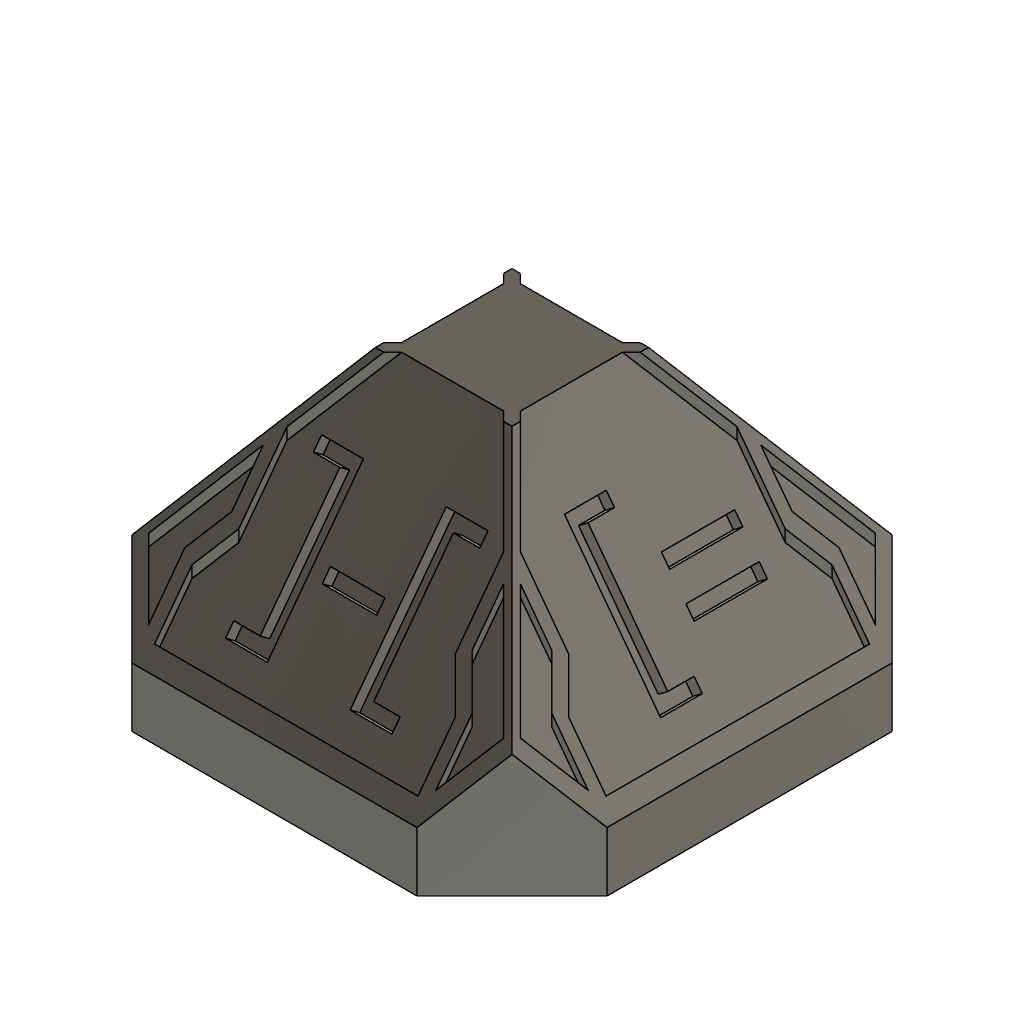
Square Piece (Autodesk Fusion 360 design; units mm, degrees)
part number: 2026-10-12-20-49-09-921
Autodesk Fusion 360 part; units mm, degrees
note: some values were not read from the file. Set by a fixed rule: which face or edge a step refers to.
sketch "Sketch1" plane through (0, 0, 0) normal (0, 0, 1) x (1, 0, 0)
  line L0 (-10, 10) -> (10, 10)
  line L1 (10, 10) -> (10, -10)
  line L2 (10, -10) -> (-10, -10)
  line L3 (-10, -10) -> (-10, 10)
  line L4 (-2.5, 2.5) -> (2.5, 2.5)
  line L5 (2.5, 2.5) -> (2.5, -2.5)
  line L6 (2.5, -2.5) -> (-2.5, -2.5)
  line L7 (-2.5, -2.5) -> (-2.5, 2.5)
  line L8 (-6, 10) -> (-10, 6)
  line L9 (6, 10) -> (10, 6)
  line L10 (10, -6) -> (6, -10)
  line L11 (-10, -6) -> (-6, -10)
  line L12 (-2.5, 2.5) -> (-8, 8)
  line L13 (2.5, 2.5) -> (8, 8)
  line L14 (2.5, -2.5) -> (8, -8)
  line L15 (-2.5, -2.5) -> (-8, -8)
  line L16 (-6.5, 9.5) -> (6.5, 9.5)
  line L17 (9.5, 6.5) -> (9.5, -6.5)
  line L18 (6.5, -9.5) -> (-6.5, -9.5)
  line L19 (-9.5, -6.5) -> (-9.5, 6.5)
  line L20 (-10, 5.2929) -> (-5.2929, 10)
  line L21 (5.2929, 10) -> (10, 5.2929)
  line L22 (10, -5.2929) -> (5.2929, -10)
  line L23 (-5.2929, -10) -> (-10, -5.2929)
  line L24 (2.1464, 2.5) -> (7.4697, 7.8232)
  line L25 (2.5, 2.1464) -> (7.8232, 7.4697)
  line L26 (-2.1464, 2.5) -> (-7.4697, 7.8232)
  line L27 (-2.5, 2.1464) -> (-7.8232, 7.4697)
  line L28 (-2.5, -2.1464) -> (-7.8232, -7.4697)
  line L29 (-2.1464, -2.5) -> (-7.4697, -7.8232)
  line L30 (2.1464, -2.5) -> (7.4697, -7.8232)
  line L31 (2.5, -2.1464) -> (7.8232, -7.4697)
  line L32 (6.4545, 8.8384) -> (4.2354, 6.6193)
  line L33 (6.8081, 8.4848) -> (4.4937, 6.1705)
  line L34 (5.7929, 9.5) -> (5.0889, 8.796)
  line L35 (8.4848, 6.8081) -> (5.9884, 4.3116)
  line L36 (8.8384, 6.4545) -> (6.602, 4.2182)
  line L37 (4.8081, 5.1616) -> (4.8081, 5.9)
  line L38 (5.1616, 4.8081) -> (5.9, 4.8081)
  line L39 (4.5581, 4.9116) -> (4.5581, 6.9428)
  line L40 (5.0581, 5.4116) -> (5.0581, 6.7348)
  line L41 (5.4116, 5.0581) -> (6.7348, 5.0581)
  line L42 (4.9116, 4.5581) -> (6.9419, 4.5581)
  line L43 (9.5, 5.7929) -> (8.9687, 5.2616)
  line L44 (2.5, 0) -> (9.5, 0)
  line L45 (2.5, -2.5) -> (8, -8)
  line L46 (8.4848, -6.8081) -> (5.9884, -4.3116)
  line L47 (6, -10) -> (10, -6)
  line L48 (5.2929, -10) -> (10, -5.2929)
  line L49 (2.5, -2.1464) -> (7.8232, -7.4697)
  line L50 (6.4545, -8.8384) -> (4.2354, -6.6193)
  line L51 (4.8081, -5.1616) -> (4.8081, -5.9)
  line L52 (9.5, -5.7929) -> (8.9687, -5.2616)
  line L53 (5.1616, -4.8081) -> (5.9, -4.8081)
  line L54 (6.8081, -8.4848) -> (4.4937, -6.1705)
  line L55 (5.7929, -9.5) -> (5.0889, -8.796)
  line L56 (2.1464, -2.5) -> (7.4697, -7.8232)
  line L57 (4.5581, -4.9116) -> (4.5581, -6.9428)
  line L58 (5.0581, -5.4116) -> (5.0581, -6.7348)
  line L59 (4.9116, -4.5581) -> (6.9419, -4.5581)
  line L60 (5.4116, -5.0581) -> (6.7348, -5.0581)
  line L61 (8.8384, -6.4545) -> (6.602, -4.2182)
  line L62 (0, 2.5) -> (0, 9.5)
  line L63 (0, -2.5) -> (0, -9.5)
  line L64 (-4.5581, 4.9116) -> (-4.5581, 6.9428)
  line L65 (-5.2929, 10) -> (-10, 5.2929)
  line L66 (-8.8384, 6.4545) -> (-6.602, 4.2182)
  line L67 (-5.4116, 5.0581) -> (-6.7348, 5.0581)
  line L68 (-4.9116, 4.5581) -> (-6.9419, 4.5581)
  line L69 (-2.1464, 2.5) -> (-7.4697, 7.8232)
  line L70 (-6.4545, 8.8384) -> (-4.2354, 6.6193)
  line L71 (-4.8081, 5.1616) -> (-4.8081, 5.9)
  line L72 (-9.5, 5.7929) -> (-8.9687, 5.2616)
  line L73 (-5.7929, 9.5) -> (-5.0889, 8.796)
  line L74 (-5.0581, 5.4116) -> (-5.0581, 6.7348)
  line L75 (-2.5, 2.1464) -> (-7.8232, 7.4697)
  line L76 (-6, 10) -> (-10, 6)
  line L77 (-5.1616, 4.8081) -> (-5.9, 4.8081)
  line L78 (-2.5, 2.5) -> (-8, 8)
  line L79 (-8.4848, 6.8081) -> (-5.9884, 4.3116)
  line L80 (-6.8081, 8.4848) -> (-4.4937, 6.1705)
  line L81 (-10, -5.2929) -> (-5.2929, -10)
  line L82 (-10, 10) -> (-10, -10)
  line L83 (-4.8081, -5.1616) -> (-4.8081, -5.9)
  line L84 (-9.5, 6.5) -> (-9.5, -6.5)
  line L85 (-8.4848, -6.8081) -> (-5.9884, -4.3116)
  line L86 (-5.7929, -9.5) -> (-5.0889, -8.796)
  line L87 (-9.5, -5.7929) -> (-8.9687, -5.2616)
  line L88 (-5.4116, -5.0581) -> (-6.7348, -5.0581)
  line L89 (-2.1464, -2.5) -> (-7.4697, -7.8232)
  line L90 (-10, -6) -> (-6, -10)
  line L91 (-6, -10) -> (-10, -6)
  line L92 (-2.5, -2.1464) -> (-7.8232, -7.4697)
  line L93 (-4.5581, -4.9116) -> (-4.5581, -6.9428)
  line L94 (-2.5, -2.5) -> (-8, -8)
  line L95 (-2.5, -2.5) -> (-8, -8)
  line L96 (-5.1616, -4.8081) -> (-5.9, -4.8081)
  line L97 (-8.8384, -6.4545) -> (-6.602, -4.2182)
  line L98 (-5.0581, -5.4116) -> (-5.0581, -6.7348)
  line L99 (-2.5, -2.1464) -> (-7.8232, -7.4697)
  line L100 (-6.8081, -8.4848) -> (-4.4937, -6.1705)
  line L101 (-4.9116, -4.5581) -> (-6.9419, -4.5581)
  line L102 (-5.2929, -10) -> (-10, -5.2929)
  line L103 (-6.4545, -8.8384) -> (-4.2354, -6.6193)
  line L104 (-2.1464, -2.5) -> (-7.4697, -7.8232)
  line L105 (5.7929, 9.5) -> (5.7929, 8.1768)
  line L106 (5.5429, 9.5) -> (5.5429, 7.9268)
  line L107 (6.0429, 9.25) -> (6.0429, 7.7197)
  line L108 (9.5, 5.7929) -> (8.1768, 5.7929)
  line L109 (7.9268, 5.5429) -> (9.5, 5.5429)
  line L110 (7.7197, 6.0429) -> (9.25, 6.0429)
  line L111 (7.7197, -6.0429) -> (9.25, -6.0429)
  line L112 (9.5, -5.7929) -> (8.1768, -5.7929)
  line L113 (7.9268, -5.5429) -> (9.5, -5.5429)
  line L114 (5.5429, -9.5) -> (5.5429, -7.9268)
  line L115 (5.7929, -9.5) -> (5.7929, -8.1768)
  line L116 (6.0429, -9.25) -> (6.0429, -7.7197)
  line L117 (-7.7197, -6.0429) -> (-9.25, -6.0429)
  line L118 (-9.5, -5.7929) -> (-8.1768, -5.7929)
  line L119 (-7.9268, -5.5429) -> (-9.5, -5.5429)
  line L120 (-6.0429, -9.25) -> (-6.0429, -7.7197)
  line L121 (-5.7929, -9.5) -> (-5.7929, -8.1768)
  line L122 (-5.5429, -9.5) -> (-5.5429, -7.9268)
  line L123 (-7.9268, 5.5429) -> (-9.5, 5.5429)
  line L124 (-9.5, 5.7929) -> (-8.1768, 5.7929)
  line L125 (-7.7197, 6.0429) -> (-9.25, 6.0429)
  line L126 (-6.0429, 9.25) -> (-6.0429, 7.7197)
  line L127 (-5.7929, 9.5) -> (-5.7929, 8.1768)
  line L128 (-5.5429, 9.5) -> (-5.5429, 7.9268)
  point P0 (10, -10)
  point P1 (9.5, -6.5)
  point P2 (6.5, -9.5)
  point P3 (-6.5, 9.5)
  point P4 (-6.5, -9.5)
  point P5 (-6.5, -9.5)
  point P6 (-9.5, -6.5)
  point P7 (-10, -10)
  dimension "d1" = 0.5
  dimension "d2" = 0.5
  dimension "d3" = 0.5
  dimension "d4" = 0.5
  dimension "d5" = 0.25
  dimension "d6" = 0.25
  dimension "d7" = 0.25
  dimension "d8" = 0.25
  dimension "d9" = 0.25
  dimension "d10" = 0.25
  dimension "d11" = 0.25
  dimension "d12" = 0.25
  dimension "d13" = 0.5
  dimension "d17" = 0.5
  dimension "d18" = 0.5
  dimension "d19" = 0.5
  dimension "d20" = 0.5
  dimension "d21" = 4
  dimension "d22" = 4
  dimension "d23" = 4
  dimension "d24" = 4
  dimension "d25" = 4
  dimension "d26" = 20
  dimension "d27" = 20
  dimension "d28" = 4
  dimension "d29" = 4
  dimension "d30" = 4
  dimension "d31" = 0.9357
  dimension "d32" = 0.9357
  dimension "d33" = 0.5
  dimension "d39" = 2.5
  dimension "d40" = 2.5
  dimension "d41" = 2.5
  dimension "d42" = 2.5
  dimension "d46" = 3.7641
  dimension "d47" = 3.7641
  dimension "d48" = 3.7641
  dimension "d49" = 3.7641
  dimension "d50" = 0.25
  dimension "d51" = 0.25
  dimension "d52" = 0.25
  dimension "d53" = 0.25
  dimension "d54" = 0.9357
  dimension "d55" = 0.9357
  dimension "d75" = 0.25
  dimension "d76" = 0.25
  dimension "d77" = 0.25
  dimension "d78" = 0.25
  constraint horizontal L0
  constraint vertical L1
  constraint horizontal L2
  constraint vertical L3
  constraint horizontal L4
  constraint vertical L5
  constraint horizontal L6
  constraint vertical L7
  constraint coincident L0 L8.start
  constraint coincident L3 L8.end
  constraint coincident L0 L9.start
  constraint coincident L1 L9.end
  constraint perpendicular L8 L9
  constraint coincident L1 L10.start
  constraint coincident L2 L10.end
  constraint parallel L8 L10
  constraint coincident L3 L11.start
  constraint coincident L2 L11.end
  constraint perpendicular L10 L11
  constraint midpoint L8 L12.end
  constraint perpendicular L8 L12
  constraint midpoint L9 L13.end
  constraint perpendicular L9 L13
  constraint midpoint L10 L14.end
  constraint perpendicular L10 L14
  constraint midpoint L11 L15.end
  constraint perpendicular L11 L15
  constraint coincident L8 P3
  constraint coincident L9 L16.end
  constraint parallel L0 L16
  constraint coincident L9 L17.start
  constraint coincident L10 P1
  constraint perpendicular L16 L17
  constraint coincident L10 P2
  constraint coincident L11 P5
  constraint perpendicular L1 L18
  constraint coincident L11 P6
  constraint coincident L8 L19.end
  constraint perpendicular L18 L19
  constraint coincident L3 L20.start
  constraint coincident L0 L20.end
  constraint coincident L0 L21.start
  constraint coincident L1 L21.end
  constraint perpendicular L13 L21
  constraint coincident L1 L22.start
  constraint coincident L2 L22.end
  constraint perpendicular L21 L22
  constraint coincident L2 L23.start
  constraint coincident L3 L23.end
  constraint perpendicular L22 L23
  constraint coincident L4 L24.start
  constraint coincident L21 L24.end
  constraint perpendicular L21 L24
  constraint coincident L5 L25.start
  constraint coincident L21 L25.end
  constraint perpendicular L21 L25
  constraint coincident L4 L26.start
  constraint coincident L20 L26.end
  constraint perpendicular L20 L26
  constraint coincident L7 L27.start
  constraint coincident L20 L27.end
  constraint perpendicular L20 L27
  constraint coincident L7 L28.start
  constraint coincident L23 L28.end
  constraint perpendicular L23 L28
  constraint coincident L6 L29.start
  constraint coincident L23 L29.end
  constraint perpendicular L23 L29
  constraint coincident L6 L30.start
  constraint coincident L22 L30.end
  constraint perpendicular L22 L30
  constraint coincident L5 L31.start
  constraint coincident L22 L31.end
  constraint perpendicular L22 L31
  constraint coincident L21 L32.start
  constraint perpendicular L21 L32
  constraint coincident L21 L33.start
  constraint perpendicular L21 L33
  constraint coincident L21 L34.start
  constraint coincident L16 L34.start
  constraint perpendicular L21 L34
  constraint coincident L21 L35.start
  constraint perpendicular L21 L35
  constraint coincident L21 L36.start
  constraint perpendicular L21 L36
  constraint coincident L24 L37.start
  constraint vertical L37
  constraint coincident L25 L38.start
  constraint horizontal L38
  constraint coincident L24 L39.start
  constraint vertical L39
  constraint coincident L24 L40.start
  constraint parallel L37 L40
  constraint coincident L33 L40.end
  constraint coincident L25 L41.start
  constraint horizontal L41
  constraint coincident L25 L42.start
  constraint horizontal L42
  constraint coincident L21 L43.start
  constraint coincident L17 L43.start
  constraint perpendicular L21 L43
  constraint coincident L36 L42.end
  constraint coincident L35 L41.end
  constraint midpoint L5 L44.start
  constraint midpoint L17 L44.end
  constraint symmetric L0.end L44 P0
  constraint symmetric L4.end L44 L5.end
  constraint symmetric L9.start L44 L10.end
  constraint symmetric L9.end L44 L10.start
  constraint symmetric L13.end L44 L14.end
  constraint symmetric L16.end L44 P2
  constraint symmetric L17.start L44 P1
  constraint symmetric L21.start L44 L22.end
  constraint symmetric L21.end L44 L22.start
  constraint symmetric L24.start L44 L30.start
  constraint symmetric L24.end L44 L30.end
  constraint symmetric L25.start L44 L31.start
  constraint symmetric L25.end L44 L31.end
  constraint symmetric L32.start L44 L50.start
  constraint symmetric L32.end L44 L50.end
  constraint symmetric L33.start L44 L54.start
  constraint symmetric L33.end L44 L54.end
  constraint symmetric L34.start L44 L55.start
  constraint symmetric L34.end L44 L55.end
  constraint symmetric L35.start L44 L46.start
  constraint symmetric L35.end L44 L46.end
  constraint symmetric L36.start L44 L61.start
  constraint symmetric L36.end L44 L61.end
  constraint symmetric L37.start L44 L51.start
  constraint symmetric L37.end L44 L51.end
  constraint symmetric L38.start L44 L53.start
  constraint symmetric L38.end L44 L53.end
  constraint symmetric L39.start L44 L57.start
  constraint symmetric L39.end L44 L57.end
  constraint symmetric L40.start L44 L58.start
  constraint symmetric L40.end L44 L58.end
  constraint symmetric L41.start L44 L60.start
  constraint symmetric L41.end L44 L60.end
  constraint symmetric L42.start L44 L59.start
  constraint symmetric L42.end L44 L59.end
  constraint symmetric L43.start L44 L52.start
  constraint symmetric L43.end L44 L52.end
  constraint midpoint L4 L62.start
  constraint midpoint L16 L62.end
  constraint midpoint L6 L63.start
  constraint midpoint L18 L63.end
  constraint symmetric L0.end L62 L0.start
  constraint symmetric P0 L62 P7
  constraint symmetric L4.end L62 L4.start
  constraint symmetric L5.end L62 L6.end
  constraint symmetric L9.start L62 L8.start
  constraint symmetric L9.end L62 L8.end
  constraint symmetric L10.start L62 L11.start
  constraint symmetric L10.end L62 L11.end
  constraint symmetric L13.end L62 L12.end
  constraint symmetric L14.end L62 L15.end
  constraint symmetric L16.end L62 P3
  constraint symmetric L17.start L62 L19.end
  constraint symmetric P1 L62 P6
  constraint symmetric P2 L62 P5
  constraint symmetric L21.start L62 L20.end
  constraint symmetric L21.end L62 L20.start
  constraint symmetric L22.start L62 L23.end
  constraint symmetric L22.end L62 L23.start
  constraint symmetric L24.start L62 L26.start
  constraint symmetric L24.end L62 L26.end
  constraint symmetric L25.start L62 L27.start
  constraint symmetric L25.end L62 L27.end
  constraint symmetric L30.start L62 L29.start
  constraint symmetric L30.end L62 L29.end
  constraint symmetric L31.start L62 L28.start
  constraint symmetric L31.end L62 L28.end
  constraint symmetric L32.start L62 L70.start
  constraint symmetric L32.end L62 L70.end
  constraint symmetric L33.start L62 L80.start
  constraint symmetric L33.end L62 L80.end
  constraint symmetric L34.start L62 L73.start
  constraint symmetric L34.end L62 L73.end
  constraint symmetric L35.start L62 L79.start
  constraint symmetric L35.end L62 L79.end
  constraint symmetric L36.start L62 L66.start
  constraint symmetric L36.end L62 L66.end
  constraint symmetric L37.start L62 L71.start
  constraint symmetric L37.end L62 L71.end
  constraint symmetric L38.start L62 L77.start
  constraint symmetric L38.end L62 L77.end
  constraint symmetric L39.start L62 L64.start
  constraint symmetric L39.end L62 L64.end
  constraint symmetric L40.start L62 L74.start
  constraint symmetric L40.end L62 L74.end
  constraint symmetric L41.start L62 L67.start
  constraint symmetric L41.end L62 L67.end
  constraint symmetric L42.start L62 L68.start
  constraint symmetric L42.end L62 L68.end
  constraint symmetric L43.start L62 L72.start
  constraint symmetric L43.end L62 L72.end
  constraint symmetric L59.end L62 L101.end
  constraint symmetric L60.end L62 L88.end
  constraint symmetric L59.start L62 L101.start
  constraint symmetric L60.start L62 L88.start
  constraint symmetric L58.start L62 L98.start
  constraint symmetric L52.start L62 L87.start
  constraint symmetric L57.start L62 L93.start
  constraint symmetric L53.start L62 L96.start
  constraint symmetric L51.start L62 L83.start
  constraint symmetric L58.end L62 L98.end
  constraint symmetric L61.start L62 L97.start
  constraint symmetric L55.end L62 L86.end
  constraint symmetric L50.start L62 L103.start
  constraint symmetric L46.start L62 L85.start
  constraint symmetric L55.start L62 L86.start
  constraint symmetric L54.start L62 L100.start
  constraint symmetric L57.end L62 L93.end
  constraint symmetric L54.end L62 L100.end
  constraint symmetric L46.end L62 L85.end
  constraint symmetric L51.end L62 L83.end
  constraint symmetric L50.end L62 L103.end
  constraint symmetric L61.end L62 L97.end
  constraint symmetric L52.end L62 L87.end
  constraint symmetric L53.end L62 L96.end
  constraint coincident L32 L105.end
  constraint vertical L105
  constraint coincident L16 L106.start
  constraint coincident L32 L106.end
  constraint perpendicular L16 L106
  constraint coincident L21 L107.start
  constraint coincident L33 L107.end
  constraint parallel L106 L107
  constraint coincident L36 L108.end
  constraint horizontal L108
  constraint coincident L36 L109.start
  constraint coincident L17 L109.end
  constraint perpendicular L17 L109
  constraint coincident L35 L110.start
  constraint coincident L21 L110.end
  constraint horizontal L110
  constraint symmetric L44 L105.end L115.end
  constraint symmetric L44 L106.start L114.start
  constraint symmetric L44 L106.end L114.end
  constraint symmetric L44 L107.start L116.start
  constraint symmetric L44 L107.end L116.end
  constraint symmetric L44 L108.end L112.end
  constraint symmetric L44 L109.start L113.start
  constraint symmetric L44 L109.end L113.end
  constraint symmetric L44 L110.start L111.start
  constraint symmetric L44 L110.end L111.end
  constraint symmetric L62 L105.end L127.end
  constraint symmetric L62 L106.start L128.start
  constraint symmetric L62 L106.end L128.end
  constraint symmetric L62 L107.start L126.start
  constraint symmetric L62 L107.end L126.end
  constraint symmetric L62 L108.end L124.end
  constraint symmetric L62 L109.start L123.start
  constraint symmetric L62 L109.end L123.end
  constraint symmetric L62 L110.start L125.start
  constraint symmetric L62 L110.end L125.end
  constraint symmetric L62 L111.start L117.start
  constraint symmetric L62 L111.end L117.end
  constraint symmetric L62 L52.start L87.start
  constraint symmetric L62 L112.end L118.end
  constraint symmetric L62 L113.start L119.start
  constraint symmetric L62 L113.end L119.end
  constraint symmetric L62 L114.start L122.start
  constraint symmetric L62 L114.end L122.end
  constraint symmetric L62 L55.start L86.start
  constraint symmetric L62 L115.end L121.end
  constraint symmetric L62 L116.start L120.start
  constraint symmetric L62 L116.end L120.end
  measures "d1" distance of L8 L20
  measures "d2" distance of L9 L21
  measures "d3" distance of L10 L22
  measures "d4" distance of L11 L23
  measures "d5" distance of L13 L24
  measures "d6" distance of L13 L25
  measures "d7" distance of L12 L26
  measures "d8" distance of L12 L27
  measures "d9" distance of L14 L31
  measures "d10" distance of L14 L30
  measures "d11" distance of L15 L29
  measures "d12" distance of L15 L28
  measures "d13" distance of L32 L33
  measures "d17" distance of L0 L16
  measures "d18" distance of L1 L17
  measures "d19" distance of L2 L18
  measures "d20" distance of L3 L19
  measures "d21" distance of L0.end L9.start
  measures "d22" distance of L0.end L9.end
  measures "d23" distance of P0 L10.start
  measures "d24" distance of L0.start L8.start
  measures "d25" distance of P7 L11.start
  measures "d26" distance of L0 L2
  measures "d27" distance of L1 L3
  measures "d28" distance of L0.start L8.end
  measures "d29" distance of P0 L10.end L5
  measures "d30" distance of P7 L11.end
  measures "d31" distance of L24 L33
  measures "d32" distance of L32 L34
  measures "d33" distance of L35 L36
  measures "d39" distance of origin L4
  measures "d40" distance of origin L7
  measures "d41" distance of origin L5
  measures "d42" distance of origin L6
  measures "d46" distance of L21 L37.start
  measures "d47" distance of L24.start L37.start
  measures "d48" distance of L25.start L38.start
  measures "d49" distance of L21 L38.start
  measures "d50" distance of L37 L39
  measures "d51" distance of L37 L40
  measures "d52" distance of L38 L41
  measures "d53" distance of L38 L42
  measures "d54" distance of L36 L43
  measures "d55" distance of L25 L35
  measures "d75" distance of L105 L106
  measures "d76" distance of L105 L107
  measures "d77" distance of L108 L110
  measures "d78" distance of L108 L109
extrude "Extrude1" add sketch "Sketch1" along normal blind 12 contours L0 L8 L16 L20 L65 L76 | L3 L8 L19 L20 L65 L76 L82 L84 | L0 L16 L20 L21 L65 | L8 L12 L16 L20 L65 L76 L78 | L3 L19 L20 L23 L65 L81 L82 L84 L102 | L8 L12 L19 L20 L65 L76 L78 L84 | L0 L9 L16 L21 | L20 L65 L70 L126 L127 | L16 L73 L128 | L70 L73 L127 L128 | L3 L11 L19 L23 L81 L82 L84 L90 L91 L102 | L19 L72 L84 L123 | L66 L72 L123 L124 | L20 L65 L66 L124 L125 | L16 L34 L106 | L9 L13 L16 L21 | L32 L34 L105 L106 | L21 L32 L105 L107 | L4 L16 L26 L62 L64 L69 L70 L128 | L20 L65 L70 L126 | L64 L70 L80 L126 | L4 L12 L20 L26 L65 L69 L78 | L7 L12 L20 L27 L65 L75 L78 | L11 L15 L19 L23 L81 L84 L90 L91 L94 L95 L102 | L23 L81 L97 L102 L117 L118 | L19 L84 L87 L119 | L87 L97 L118 L119 | L7 L19 L27 L28 L66 L68 L75 L84 L92 L97 L99 L101 L119 L123 | L20 L65 L66 L125 | L66 L68 L79 L125 | L4 L16 L24 L32 L39 L62 L106 | L21 L32 L107 | L32 L33 L39 L107 | L20 L65 L70 L80 L126 | L4 L5 L6 L7 | L20 L27 L65 L67 L75 L79 | L20 L26 L65 L69 L74 L80 | L23 L81 L97 L102 L117 | L85 L97 L101 L117 | L20 L65 L66 L79 L125 | L1 L9 L17 L21 | L9 L13 L17 L21 | L21 L32 L33 L107 | L27 L67 L68 L75 L79 | L26 L64 L69 L74 L80 | L2 L11 L18 L23 L81 L90 L91 L102 | L11 L15 L18 L23 L81 L90 L91 L94 L95 L102 | L23 L81 L85 L97 L102 L117 | L1 L17 L21 L22 L48 | L5 L13 L21 L25 | L4 L13 L21 L24 | L21 L24 L33 L40 | L7 L15 L23 L28 L81 L92 L94 L95 L99 L102 | L2 L18 L22 L23 L48 L81 L102 | L6 L15 L23 L29 L81 L89 L94 L95 L102 L104 | L23 L28 L81 L85 L88 L92 L99 L102 | L1 L10 L17 L22 L47 L48 | L21 L36 L108 L110 | L17 L43 L109 | L36 L43 L108 L109 | L21 L25 L35 L41 | L24 L33 L39 L40 | L28 L85 L88 L92 L99 L101 | L2 L10 L18 L22 L47 L48 | L18 L86 L122 | L86 L103 L121 L122 | L23 L81 L102 L103 L120 L121 | L23 L29 L81 L89 L98 L100 L102 L104 | L17 L52 L113 | L10 L14 L17 L22 L45 L47 L48 | L52 L61 L112 L113 | L22 L48 L61 L111 L112 | L5 L17 L25 L36 L42 L44 L109 | L21 L36 L110 | L35 L36 L42 L110 | L21 L35 L36 L110 | L25 L35 L41 L42 | L6 L18 L29 L63 L89 L93 L103 L104 L122 | L10 L14 L18 L22 L45 L47 L48 | L22 L48 L50 L115 L116 | L18 L55 L114 | L50 L55 L114 L115 | L23 L81 L102 L103 L120 | L93 L100 L103 L120 | L23 L81 L100 L102 L103 L120 | L29 L89 L93 L98 L100 L104 | L5 L17 L31 L44 L49 L59 L61 L113 | L22 L48 L61 L111 | L46 L59 L61 L111 | L6 L18 L30 L50 L56 L57 L63 L114 | L22 L48 L50 L116 | L50 L54 L57 L116 | L22 L46 L48 L61 L111 | L5 L14 L22 L31 L45 L48 L49 | L6 L14 L22 L30 L45 L48 L56 | L22 L48 L50 L54 L116 | L22 L31 L46 L48 L49 L60 | L31 L46 L49 L59 L60 | L30 L54 L56 L57 L58 | L22 L30 L48 L54 L56 L58 makes body 1
extrude "Extrude2" add sketch "Sketch1" along normal blind 12 separate body contours L0 L8 L16 L20 L65 L76 | L3 L8 L19 L20 L65 L76 L82 L84 | L0 L16 L20 L21 L65 | L8 L12 L16 L20 L65 L76 L78 | L3 L19 L20 L23 L65 L81 L82 L84 L102 | L8 L12 L19 L20 L65 L76 L78 L84 | L0 L9 L16 L21 | L20 L65 L70 L126 L127 | L16 L73 L128 | L70 L73 L127 L128 | L3 L11 L19 L23 L81 L82 L84 L90 L91 L102 | L19 L72 L84 L123 | L66 L72 L123 L124 | L20 L65 L66 L124 L125 | L16 L34 L106 | L9 L13 L16 L21 | L32 L34 L105 L106 | L21 L32 L105 L107 | L64 L70 L80 L126 | L4 L12 L20 L26 L65 L69 L78 | L7 L12 L20 L27 L65 L75 L78 | L11 L15 L19 L23 L81 L84 L90 L91 L94 L95 L102 | L23 L81 L97 L102 L117 L118 | L19 L84 L87 L119 | L87 L97 L118 L119 | L66 L68 L79 L125 | L32 L33 L39 L107 | L4 L5 L6 L7 | L85 L97 L101 L117 | L1 L9 L17 L21 | L9 L13 L17 L21 | L27 L67 L68 L75 L79 | L26 L64 L69 L74 L80 | L2 L11 L18 L23 L81 L90 L91 L102 | L11 L15 L18 L23 L81 L90 L91 L94 L95 L102 | L1 L17 L21 L22 L48 | L5 L13 L21 L25 | L4 L13 L21 L24 | L7 L15 L23 L28 L81 L92 L94 L95 L99 L102 | L2 L18 L22 L23 L48 L81 L102 | L6 L15 L23 L29 L81 L89 L94 L95 L102 L104 | L1 L10 L17 L22 L47 L48 | L21 L36 L108 L110 | L17 L43 L109 | L36 L43 L108 L109 | L24 L33 L39 L40 | L28 L85 L88 L92 L99 L101 | L2 L10 L18 L22 L47 L48 | L18 L86 L122 | L86 L103 L121 L122 | L23 L81 L102 L103 L120 L121 | L17 L52 L113 | L10 L14 L17 L22 L45 L47 L48 | L52 L61 L112 L113 | L22 L48 L61 L111 L112 | L35 L36 L42 L110 | L25 L35 L41 L42 | L10 L14 L18 L22 L45 L47 L48 | L22 L48 L50 L115 L116 | L18 L55 L114 | L50 L55 L114 L115 | L93 L100 L103 L120 | L29 L89 L93 L98 L100 L104 | L46 L59 L61 L111 | L50 L54 L57 L116 | L5 L14 L22 L31 L45 L48 L49 | L6 L14 L22 L30 L45 L48 L56 | L31 L46 L49 L59 L60 | L30 L54 L56 L57 L58 makes body 2
extrude "Extrude3" add sketch "Sketch1" along normal blind 12 separate body makes body 3
move_body "Move1" bodies 3 to x (1, 0, 0) y (0, 1, 0) z (0, 0, 1) at (0, 0, 7)
move_body "Move2" bodies 3 to x (1, 0, 0) y (0, 1, 0) z (0, 0, 1) at (0, 0, -7)
chamfer "Chamfer1" distance 7.5 distance2 10 104 faces at (-8.1667, 9.1667, 12) (-6.0976, 9.6667, 12) (-7.1027, 8.6616, 12) (-8.6616, 7.1027, 12) (-9.8333, 5.6953, 12) (0, 9.8333, 12) (-5.8762, 8.9756, 12) (-6.1801, 8.8384, 12) (-6.2979, 8.2104, 12) (-6.1902, 6.9848, 12) (-5.0682, 5.186, 12) (-5.0194, 4.9015, 12) (-6.9848, 6.1902, 12) (-8.2104, 6.2979, 12) (-8.8384, 6.1801, 12) (-8.9756, 5.8762, 12) (-9.6667, 1.7643, 12) (5.6953, 9.8333, 12) (5.6262, 9.4167, 12) (1.5194, 6.0783, 12) (-1.5194, 6.0783, 12) (-5.6262, 9.4167, 12) (-5.6262, 8.4512, 12) (-5.053, 7.2015, 12) (-4.8914, 6.1271, 12) (0.8333, 0, 12) (-4.9899, 0.7155, 12) (-6.1271, 4.8914, 12) (-7.4604, 5.5479, 12) (-8.9756, 5.7096, 12) (-9.4167, 5.6262, 12) (-9.4167, -5.6262, 12) (-9.6667, -6.0976, 12) (8.1667, 9.1667, 12) (7.1027, 8.6616, 12) (5.6262, 8.4512, 12) (5.0531, 7.2013, 12) (4.8914, 6.1271, 12) (4.9015, 5.0194, 12) (5.0194, 4.9015, 12) (6.0783, 1.5194, 12) (6.0783, -1.5194, 12) (5.186, -5.0682, 12) (4.9015, -5.0194, 12) (1.5194, -6.0783, 12) (-1.5194, -6.0783, 12) (-4.9015, -5.0194, 12) (-5.186, -5.0682, 12) (-6.1271, -4.8914, 12) (-7.4604, -5.5479, 12) (-8.9756, -5.7096, 12) (-8.6616, -7.1027, 12) (-9.1667, -8.1667, 12) (9.6667, 6.0976, 12) (8.6616, 7.1027, 12) (6.1902, 6.9848, 12) (6.2979, 8.2104, 12) (6.1801, 8.8384, 12) (5.8762, 8.7012, 12) (6.9848, 6.1902, 12) (6.1271, 4.8914, 12) (9.8333, 0, 12) (7.4604, 5.5479, 12) (8.9756, 5.7096, 12) (9.4167, 5.6262, 12) (9.4167, -5.6262, 12) (8.9756, -5.7096, 12) (7.4604, -5.5479, 12) (6.1271, -4.8914, 12) (6.9848, -6.1902, 12) (8.6616, -7.1027, 12) (7.1027, -8.6616, 12) (6.1902, -6.9848, 12) (4.8914, -6.1271, 12) (5.053, -7.2015, 12) (5.6262, -8.4512, 12) (5.6262, -9.4167, 12) (0, -9.8333, 12) (-5.6262, -9.4167, 12) (-5.6262, -8.4512, 12) (-5.0531, -7.2013, 12) (-4.8914, -6.1271, 12) (-6.1902, -6.9848, 12) (-7.1027, -8.6616, 12) (-6.9848, -6.1902, 12) (-8.2104, -6.2979, 12) (-8.7012, -5.8762, 12) (-8.8384, -6.1801, 12) (-5.6953, -9.8333, 12) (8.9756, 5.8762, 12) (8.8384, 6.1801, 12) (8.2104, 6.2979, 12) (9.6667, -6.0976, 12) (8.9756, -5.8762, 12) (8.2104, -6.2979, 12) (8.1667, -9.1667, 12) (8.8384, -6.1801, 12) (5.8762, -8.7012, 12) (6.1801, -8.8384, 12) (6.2979, -8.2104, 12) (5.6953, -9.8333, 12) (-5.8762, -8.7012, 12) (-6.2979, -8.2104, 12) (-6.1801, -8.8384, 12) tangent chain off on bodies 3
copy_body "CopyPasteBodies2" bodies 3 makes body 4
combine "Combine1" operation intersect target body 3 tool bodies 1
move_body "Move3" bodies 4 to x (1, 0, 0) y (0, 1, 0) z (0, 0, 1) at (0, 0, 0.5)
combine "Combine2" operation intersect target body 2 tool bodies 4
combine "Combine3" operation add target body 2 tool bodies 3
sketch "Sketch2" plane through (0, -7.36, 5.52) normal (0, -0.8, 0.6) x (1, 0, 0)
  line L0 (4.5581, 4.0806) -> (2.1464, 8.1)
  line L1 (2.1464, 8.1) -> (-2.1464, 8.1)
  line L2 (-2.1464, 8.1) -> (-4.5581, 4.0806)
  line L3 (-4.5581, 4.0806) -> (-4.5581, 0.6968)
  line L4 (-4.5581, 0.6968) -> (-5.5429, -0.9446)
  line L5 (-5.5429, -0.9446) -> (-5.5429, -3.5667)
  line L6 (-5.5429, -3.5667) -> (5.5429, -3.5667)
  line L7 (5.5429, -3.5667) -> (5.5429, -0.9446)
  line L8 (5.5429, -0.9446) -> (4.5581, 0.6968)
  line L9 (4.5581, 0.6968) -> (4.5581, 4.0806)
  line L10 (-3.5, -1.9875) -> (-3.5, -1.4141)
  line L11 (-3.5, -1.4141) -> (-2.389, -1.4141)
  line L12 (-2.389, -1.4141) -> (-2.389, 4.1766)
  line L13 (-2.389, 4.1766) -> (-3.5, 4.1766)
  line L14 (-3.5, 4.1766) -> (-3.5, 4.75)
  line L15 (-3.5, 4.75) -> (-1.744, 4.75)
  line L16 (-1.744, 4.75) -> (-1.744, -1.9875)
  line L17 (-1.744, -1.9875) -> (-3.5, -1.9875)
  line L18 (-1.1533, 1.4529) -> (1.1404, 1.4529)
  line L19 (1.1404, 1.4529) -> (1.1404, 0.8795)
  line L20 (1.1404, 0.8795) -> (-1.1533, 0.8795)
  line L21 (-1.1533, 0.8795) -> (-1.1533, 1.4529)
  line L22 (1.7429, -1.9875) -> (1.7429, 4.75)
  line L23 (1.7429, 4.75) -> (3.4989, 4.75)
  line L24 (3.4989, 4.75) -> (3.4989, 4.1766)
  line L25 (3.4989, 4.1766) -> (2.388, 4.1766)
  line L26 (2.388, 4.1766) -> (2.388, -1.4141)
  line L27 (2.388, -1.4141) -> (3.4989, -1.4141)
  line L28 (3.4989, -1.4141) -> (3.4989, -1.9875)
  line L29 (3.4989, -1.9875) -> (1.7429, -1.9875)
sketch "Sketch3" plane through (7.36, 0, 5.52) normal (0.8, 0, 0.6) x (0, 1, 0)
  line L0 (4.5581, 4.0806) -> (2.1464, 8.1)
  line L1 (2.1464, 8.1) -> (-2.1464, 8.1)
  line L2 (-2.1464, 8.1) -> (-4.5581, 4.0806)
  line L3 (-4.5581, 4.0806) -> (-4.5581, 0.6968)
  line L4 (-4.5581, 0.6968) -> (-5.5429, -0.9446)
  line L5 (-5.5429, -0.9446) -> (-5.5429, -3.5667)
  line L6 (-5.5429, -3.5667) -> (5.5429, -3.5667)
  line L7 (5.5429, -3.5667) -> (5.5429, -0.9446)
  line L8 (5.5429, -0.9446) -> (4.5581, 0.6968)
  line L9 (4.5581, 0.6968) -> (4.5581, 4.0806)
  line L10 (-2.3, -1.9875) -> (-2.3, 4.75)
  line L11 (-2.3, 4.75) -> (-0.544, 4.75)
  line L12 (-0.544, 4.75) -> (-0.544, 4.1766)
  line L13 (-0.544, 4.1766) -> (-1.6549, 4.1766)
  line L14 (-1.6549, 4.1766) -> (-1.6549, -1.4141)
  line L15 (-1.6549, -1.4141) -> (-0.544, -1.4141)
  line L16 (-0.544, -1.4141) -> (-0.544, -1.9875)
  line L17 (-0.544, -1.9875) -> (-2.3, -1.9875)
  line L18 (0.3173, 1.7396) -> (0.3173, 2.313)
  line L19 (0.3173, 2.313) -> (3.3994, 2.313)
  line L20 (3.3994, 2.313) -> (3.3994, 1.7396)
  line L21 (3.3994, 1.7396) -> (0.3173, 1.7396)
  line L22 (0.3173, 0.0194) -> (0.3173, 0.5928)
  line L23 (0.3173, 0.5928) -> (3.3994, 0.5928)
  line L24 (3.3994, 0.5928) -> (3.3994, 0.0194)
  line L25 (3.3994, 0.0194) -> (0.3173, 0.0194)
sketch "Sketch4" plane through (0, 7.36, 5.52) normal (0, 0.8, 0.6) x (-1, 0, 0)
  line L0 (-2.1464, 8.1) -> (-4.5581, 4.0806)
  line L1 (-4.5581, 4.0806) -> (-4.5581, 0.6968)
  line L2 (-4.5581, 0.6968) -> (-5.5429, -0.9446)
  line L3 (-5.5429, -0.9446) -> (-5.5429, -3.5667)
  line L4 (-5.5429, -3.5667) -> (5.5429, -3.5667)
  line L5 (5.5429, -3.5667) -> (5.5429, -0.9446)
  line L6 (5.5429, -0.9446) -> (4.5581, 0.6968)
  line L7 (4.5581, 0.6968) -> (4.5581, 4.0806)
  line L8 (4.5581, 4.0806) -> (2.1464, 8.1)
  line L9 (2.1464, 8.1) -> (-2.1464, 8.1)
  line L10 (-3.25, -1.9875) -> (-1.1781, 1.3668)
  line L11 (-1.1781, 1.3668) -> (-3.2065, 4.75)
  line L12 (-3.2065, 4.75) -> (-2.4676, 4.75)
  line L13 (-2.4676, 4.75) -> (-0.642, 1.8304)
  line L14 (-0.642, 1.8304) -> (-0.642, 0.9466)
  line L15 (-0.642, 0.9466) -> (-2.4676, -1.9875)
  line L16 (-2.4676, -1.9875) -> (-3.25, -1.9875)
  line L17 (2.5155, -1.9875) -> (0.6899, 0.9466)
  line L18 (0.6899, 0.9466) -> (0.6899, 1.8304)
  line L19 (0.6899, 1.8304) -> (2.5155, 4.75)
  line L20 (2.5155, 4.75) -> (3.2545, 4.75)
  line L21 (3.2545, 4.75) -> (1.226, 1.3668)
  line L22 (1.226, 1.3668) -> (3.298, -1.9875)
  line L23 (3.298, -1.9875) -> (2.5155, -1.9875)
sketch "Sketch5" plane through (-7.36, 0, 5.52) normal (-0.8, 0, 0.6) x (0, -1, 0)
  line L0 (-2.1464, 8.1) -> (-4.5581, 4.0806)
  line L1 (-4.5581, 4.0806) -> (-4.5581, 0.6968)
  line L2 (-4.5581, 0.6968) -> (-5.5429, -0.9446)
  line L3 (-5.5429, -0.9446) -> (-5.5429, -3.5667)
  line L4 (-5.5429, -3.5667) -> (5.5429, -3.5667)
  line L5 (5.5429, -3.5667) -> (5.5429, -0.9446)
  line L6 (5.5429, -0.9446) -> (4.5581, 0.6968)
  line L7 (4.5581, 0.6968) -> (4.5581, 4.0806)
  line L8 (4.5581, 4.0806) -> (2.1464, 8.1)
  line L9 (2.1464, 8.1) -> (-2.1464, 8.1)
  line L10 (-3.5, -1.9875) -> (-0.9555, 4.75)
  line L11 (-0.9555, 4.75) -> (-0.2746, 4.75)
  line L12 (-0.2746, 4.75) -> (-2.8191, -1.9875)
  line L13 (-2.8191, -1.9875) -> (-3.5, -1.9875)
  line L14 (2.9001, -1.9875) -> (0.3556, 4.75)
  line L15 (0.3556, 4.75) -> (1.0365, 4.75)
  line L16 (1.0365, 4.75) -> (3.581, -1.9875)
  line L17 (3.581, -1.9875) -> (2.9001, -1.9875)
extrude "Extrude4" cut sketch "Sketch2" against normal blind 0.5 contours L10 L11 L12 L13 L14 L15 L16 L17 | L18 L19 L20 L21 | L22 L23 L24 L25 L26 L27 L28 L29 bodies 2
extrude "Extrude5" cut sketch "Sketch3" against normal blind 0.5 contours L10 L11 L12 L13 L14 L15 L16 L17 | L18 L19 L20 L21 | L22 L23 L24 L25 bodies 2
extrude "Extrude6" cut sketch "Sketch4" against normal blind 0.5 contours L10 L11 L12 L13 L14 L15 L16 | L17 L18 L19 L20 L21 L22 L23 bodies 2
extrude "Extrude7" cut sketch "Sketch5" against normal blind 0.5 contours L10 L11 L12 L13 | L14 L15 L16 L17 bodies 2
scale "Scale1" factor 1.794872 about (0, 0, 0) bodies 2
equation "d31 = d32"
equation "d47 = d46"
equation "d48 = d49"
equation "d55 = d54"
equation "d96 = 70 / 39"
